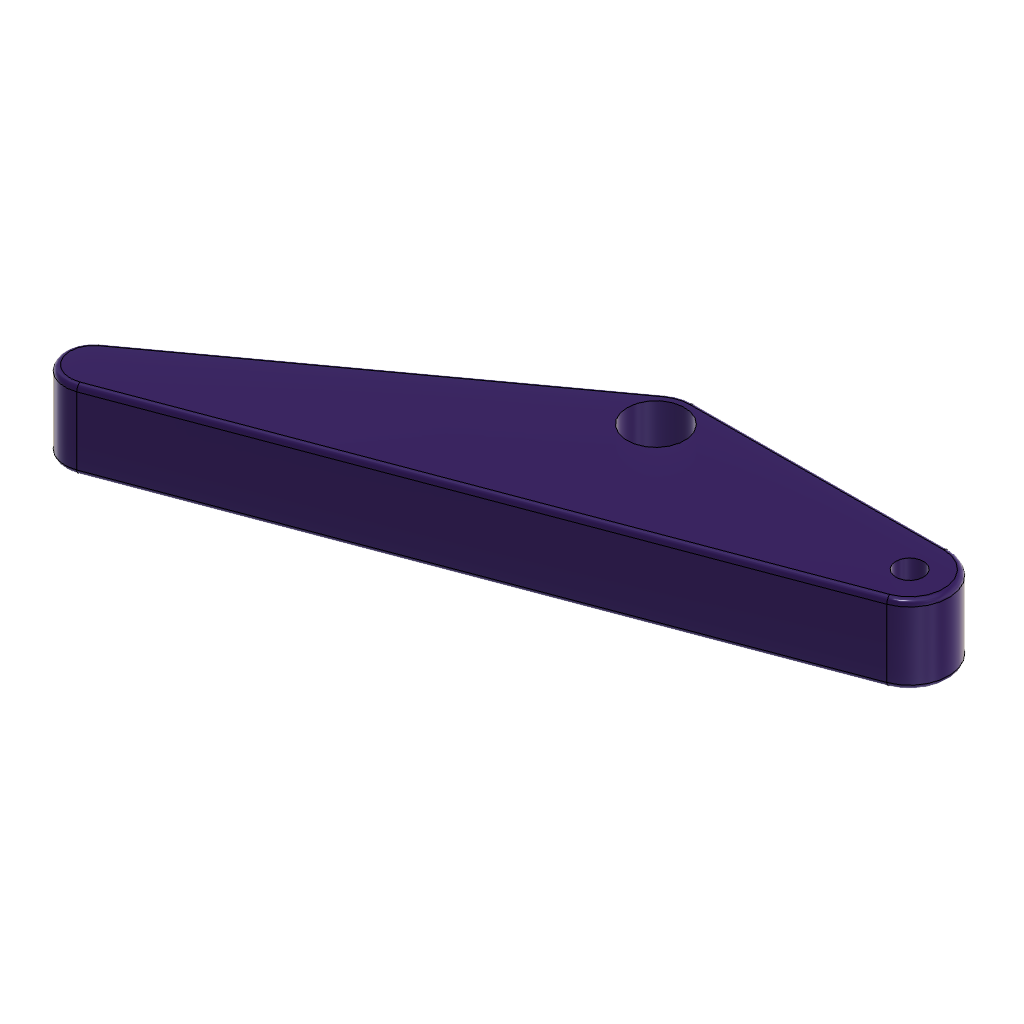
coupler_leg (Autodesk Fusion 360 design; units mm, degrees)
part number: 2026-09-20-00-02-03-166
Autodesk Fusion 360 part; units mm, degrees
sketch "Sketch1" plane through (0, 0, 0) normal (0, 0, 1) x (1, 0, 0)
  circle A0 centre (0, 0) radius 7.5
  circle A1 centre (48.4995, 0.2248) radius 7.5
  circle A2 centre (-63.9, -44.1) radius 5.5
  circle A3 centre (0, 0) radius 5.5
  circle A4 centre (48.4995, 0.2248) radius 2.65
  line L0 (-4.4176, 6.0609) -> (-67.1396, -39.6553)
  line L1 (-61.9673, -49.2492) -> (51.135, -6.7968)
  line L2 (-0.0348, 7.4999) -> (48.4647, 7.7248)
  point P0 (48.4995, 0.2248)
  point P1 (-63.9, -44.1)
  dimension "d1" = 48.5
  dimension "d2" = 44.1
  dimension "d3" = 63.9
  dimension "d4" = 15
  dimension "d5" = 15
  dimension "d6" = 11
  dimension "d7" = 11
  dimension "d8" = 5.3
  constraint coincident A0.centre A3.centre
  constraint coincident P0 A1.centre
  constraint coincident P1 A2.centre
  constraint coincident A0 L0.start
  constraint coincident A2 L0.end
  constraint tangent A2 L0
  constraint tangent A0 L0
  constraint coincident A2 L1.start
  constraint coincident A1 L1.end
  constraint tangent A1 L1
  constraint tangent A2 L1
  constraint coincident A0 L2.start
  constraint coincident A1 L2.end
  constraint tangent A1 L2
  constraint tangent A0 L2
  measures "d1" distance of A0.centre A1.centre
  measures "d2" vertical distance of A0.centre P1
  measures "d3" horizontal distance of A0.centre P1
  measures "d4" diameter of A0
  measures "d5" diameter of A1
  measures "d6" diameter of A2
  measures "d7" diameter of A3
  measures "d8" diameter of A4
extrude "Extrude1" add sketch "Sketch1" along normal blind 15
fillet "Fillet1" radius 1 12 edges at (24.215, 7.6123, 15) (-2.3396, 7.1258, 15) (-35.7786, -16.7972, 15) (-68.7412, -46.71, 15) (-5.4161, -28.023, 15) (55.8758, 1.5812, 15) (24.215, 7.6123, 0) (-2.3396, 7.1258, 0) (-35.7786, -16.7972, 0) (-68.7412, -46.71, 0) (-5.4161, -28.023, 0) (55.8758, 1.5812, 0)
